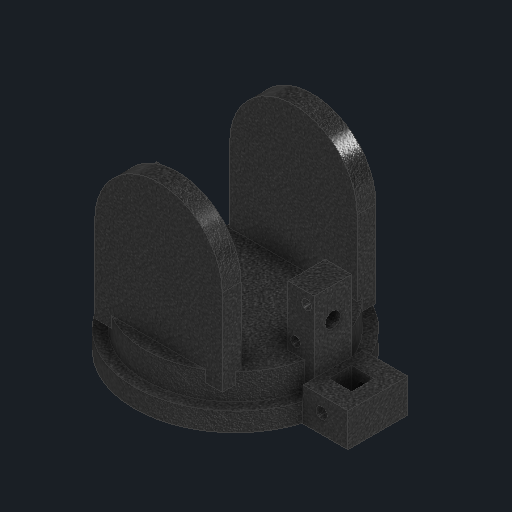
# Autodesk Inventor part: azimuth_base
Saved by Autodesk Inventor 2027.1 (Build 311270010, 270A)
## iProperties
Created: 2026-11-04
Part Number: azimuth_base
Material: Generic
Description: CG-5 azimuth base with latitude fork (estimated)
Document SubType Name: Modeling
Designer: Claude (from photos)
Density: 1 g/cm^3
Appearance: Black Cast
Author: alexg
Autodesk Inventor part; units mm, degrees
sketch "Base flange sketch" plane through (0, 0, 0) normal (0, 1, 0) x (-1, 0, 0)
  circle A0 centre (0, 0) radius 54
  constraints: 1 centre point
extrude "Base flange" add sketch "Base flange sketch" along normal blind 10
ref_plane "Work Plane1" through (0, 10, 0) normal (0, 1, 0) x (-1, 0, 0)
sketch "Base hub sketch" plane through (0, 10, 0) normal (0, 1, 0) x (-1, 0, 0)
  circle A0 centre (0, 0) radius 48
  constraints: 1 centre point
extrude "Base hub" add sketch "Base hub sketch" along normal blind 14
ref_plane "Work Plane2" through (0, 0, 31) normal (0, 0, 1) x (1, 0, 0)
sketch "Cheek +Z (logo side) sketch" plane through (0, 0, 31) normal (0, 0, 1) x (1, 0, 0)
  arc A0 (34, 64) -> (-34, 64) centre (0, 64) ccw
  line L0 (-34, 64) -> (-34, 18)
  line L1 (-34, 18) -> (34, 18)
  line L2 (34, 18) -> (34, 64)
  constraints: 6 end point, 2 point on circle, 1 centre point
extrude "Cheek +Z (logo side)" add sketch "Cheek +Z (logo side) sketch" along normal blind 10
ref_plane "Work Plane3" through (0, 0, -31) normal (0, 0, 1) x (1, 0, 0)
sketch "Cheek -Z (latitude scale side) sketch" plane through (0, 0, -31) normal (0, 0, 1) x (1, 0, 0)
  arc A0 (34, 64) -> (-34, 64) centre (0, 64) ccw
  line L0 (-34, 64) -> (-34, 18)
  line L1 (-34, 18) -> (34, 18)
  line L2 (34, 18) -> (34, 64)
  constraints: 6 end point, 2 point on circle, 1 centre point
extrude "Cheek -Z (latitude scale side)" add sketch "Cheek -Z (latitude scale side) sketch" against normal blind 10
ref_plane "Work Plane4" through (0, 0, -10) normal (0, 0, 1) x (1, 0, 0)
sketch "Latitude bolt lugs sketch" plane through (0, 0, -10) normal (0, 0, 1) x (1, 0, 0)
  line L0 (38, 12) -> (52, 12)
  line L1 (52, 12) -> (52, 56)
  line L2 (52, 56) -> (38, 56)
  line L3 (38, 56) -> (38, 12)
  line L4 (-52, 12) -> (-38, 12)
  line L5 (-38, 12) -> (-38, 56)
  line L6 (-38, 56) -> (-52, 56)
  line L7 (-52, 56) -> (-52, 12)
  constraints: 16 end point, 4 parallel, 2 horizontal, 2 perpendicular
extrude "Latitude bolt lugs" add sketch "Latitude bolt lugs sketch" along normal blind 20
ref_plane "Work Plane5" through (60, 0, 0) normal (1, 0, 0) x (0, 1, 0)
sketch "Latitude bolt threads sketch" plane through (60, 0, 0) normal (1, 0, 0) x (0, 1, 0)
  circle A0 centre (40, 0) radius 4
  constraints: 1 centre point
extrude "Latitude bolt threads" cut sketch "Latitude bolt threads sketch" against normal blind 120
ref_plane "Work Plane6" through (0, 0, 10) normal (0, 0, 1) x (1, 0, 0)
sketch "Lug M5 holes sketch" plane through (0, 0, 10) normal (0, 0, 1) x (1, 0, 0)
  circle A0 centre (42, 30) radius 2.6
  circle A1 centre (48, 50) radius 2.6
  circle A2 centre (-42, 30) radius 2.6
  circle A3 centre (-48, 50) radius 2.6
  constraints: 4 centre point
extrude "Lug M5 holes" cut sketch "Lug M5 holes sketch" against normal blind 13
ref_plane "Work Plane7" through (0, 0, -41) normal (0, 0, 1) x (1, 0, 0)
sketch "Latitude scale recess sketch" plane through (0, 0, -41) normal (0, 0, 1) x (1, 0, 0)
  circle A0 centre (0, 64) radius 23
  constraints: 1 centre point
extrude "Latitude scale recess" cut sketch "Latitude scale recess sketch" along normal blind 2
sketch "Azimuth block sketch" plane through (0, 0, 0) normal (0, 1, 0) x (-1, 0, 0)
  line L0 (-52, -16) -> (-76, -16)
  line L1 (-76, -16) -> (-76, 16)
  line L2 (-76, 16) -> (-52, 16)
  line L3 (-52, 16) -> (-52, -16)
  constraints: 8 end point, 2 parallel, 1 horizontal, 1 perpendicular
extrude "Azimuth block" add sketch "Azimuth block sketch" along normal blind 18
sketch "Azimuth peg slot sketch" plane through (0, 0, 0) normal (0, 1, 0) x (-1, 0, 0)
  line L0 (-56, -6) -> (-68, -6)
  line L1 (-68, -6) -> (-68, 6)
  line L2 (-68, 6) -> (-56, 6)
  line L3 (-56, 6) -> (-56, -6)
  constraints: 8 end point, 2 parallel, 1 horizontal, 1 perpendicular
extrude "Azimuth peg slot" cut sketch "Azimuth peg slot sketch" along normal blind 18
ref_plane "Work Plane8" through (0, 0, 20) normal (0, 0, 1) x (1, 0, 0)
sketch "Azimuth bolt threads sketch" plane through (0, 0, 20) normal (0, 0, 1) x (1, 0, 0)
  circle A0 centre (62, 10) radius 3
  constraints: 1 centre point
extrude "Azimuth bolt threads" cut sketch "Azimuth bolt threads sketch" against normal blind 40
body "Solid1"
